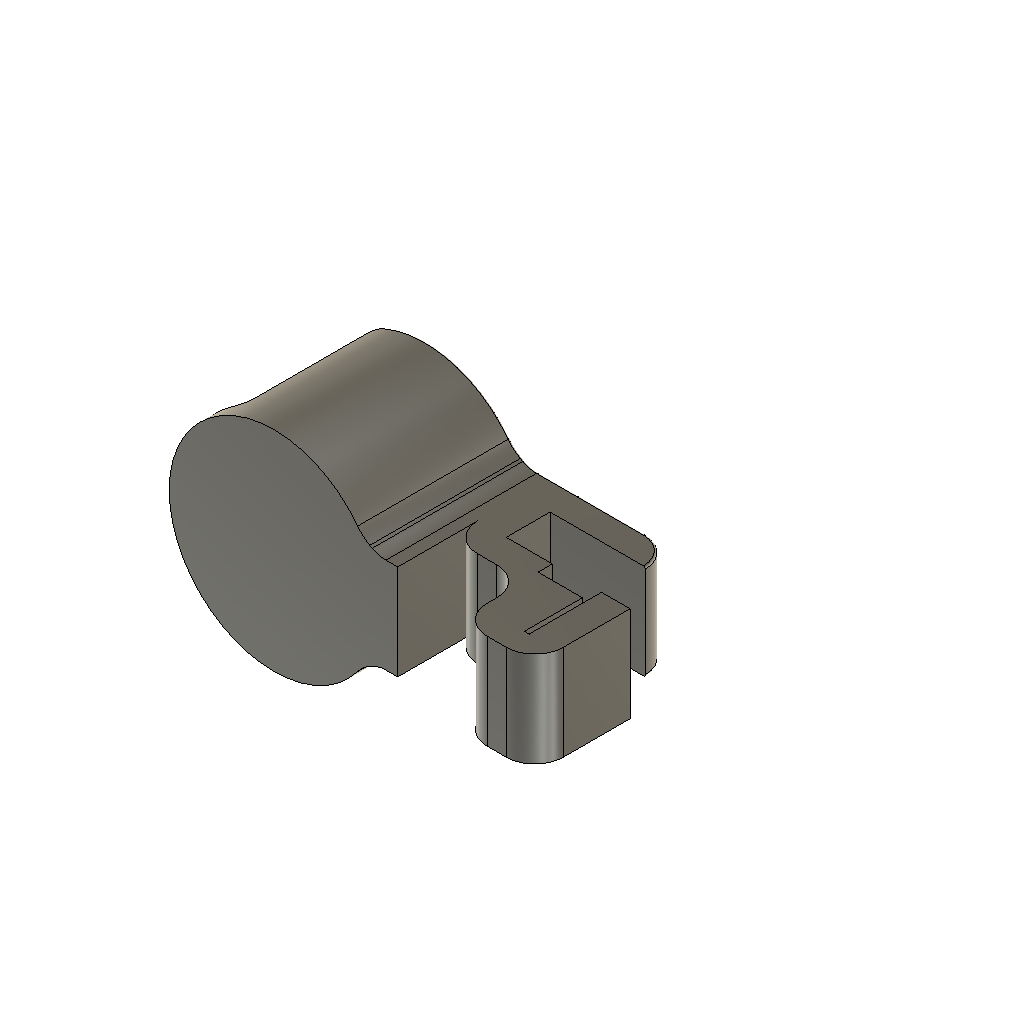
IkeaSkarstaTableGlassHolder (Autodesk Fusion 360 design; units mm, degrees)
part number: 2026-08-08-23-18-43-704
Autodesk Fusion 360 part; units mm, degrees
sketch "Sketch1" plane through (0, 0, 0) normal (0, 0, 1) x (1, 0, 0)
  line L0 (0, 0) -> (0, -38)
  line L1 (0, -38) -> (-2.5, -38)
  line L2 (-2.5, -38) -> (-2.5, -7.5)
  line L3 (-2.5, -7.5) -> (-25.8, -7.5)
  line L4 (-25.8, -7.5) -> (-25.8, 0)
  line L5 (-25.8, 0) -> (-50, 0)
  line L6 (-50, 0) -> (-50, 23)
  line L7 (-50, 23) -> (0, 23)
  line L8 (15, 0) -> (15, -38)
  line L9 (-50, 38) -> (-15, 38)
  line L10 (15, 0) -> (0, 0)
  arc A0 (0, 23) -> (-15, 38) centre (-15, 23) ccw
  line L11 (-64.9913, 38.0024) -> (-50, 38)
  line L12 (-64.9913, 38.0024) -> (-64.9976, 0.0024)
  line L13 (15, -38) -> (15, -35)
  line L14 (0, -50) -> (-10, -50)
  line L15 (-25, -35) -> (-25, -30)
  line L16 (-40, -15) -> (-49.9976, -15)
  arc A1 (-25, -30) -> (-40, -15) centre (-40, -30) ccw
  arc A2 (-64.9976, 0.0024) -> (-49.9976, -15) centre (-49.9976, 0) ccw
  arc A3 (-25, -35) -> (-10, -50) centre (-10, -35) ccw
  arc A4 (0, -50) -> (15, -35) centre (0, -35) ccw
  point P0 (-50, -80)
  dimension "d1" = 38
  dimension "d2" = 2.5
  dimension "d3" = 30.5
  dimension "d4" = 23.3
  dimension "d5" = 24.2
  dimension "d9" = 23
  dimension "d11" = 15
  dimension "d33" = 15
  dimension "d34" = 15
  dimension "d35" = 15
  dimension "d36" = 15
  constraint coincident L0.start L10.end
  constraint vertical L0
  constraint perpendicular L0 L1
  constraint perpendicular L1 L2
  constraint perpendicular L2 L3
  constraint perpendicular L3 L4
  constraint perpendicular L4 L5
  constraint perpendicular L5 L6
  constraint perpendicular L6 L7
  constraint perpendicular L0 L10
  constraint tangent L9 A0
  constraint coincident L7.end A0.start
  constraint perpendicular L11 L12
  constraint parallel L8 L13
  constraint perpendicular L13 L14
  constraint perpendicular L14 L15
  constraint parallel L14 L16
  constraint tangent L15 A1
  constraint tangent L16 A1
  constraint tangent L12 A2
  constraint tangent L16 A2
  constraint tangent L14 A3
  constraint tangent L15 A3
  constraint tangent L13 A4
  constraint tangent L14 A4
  measures "d1" distance of L0.start L0.end
  measures "d2" distance of L0.end L1.end
  measures "d3" distance of L1.end L2.end
  measures "d4" distance of L2.end L3.end
  measures "d5" distance of L4.end L5.end
  measures "d9" distance of L5.end L6.end
  measures "d11" radius of A0
  measures "d33" radius of A1
  measures "d34" radius of A2
  measures "d35" radius of A3
  measures "d36" radius of A4
extrude "Extrude5" add sketch "Sketch1" along normal blind 50
sketch "Sketch3" plane through (0.0062, 37.9918, 0) normal (0.000163, 1, 0) x (-1, 0.000163, 0)
  line L0 (50.0062, 0) -> (64.9976, 0)
  line L1 (64.9976, 0) -> (64.9976, 50)
  line L2 (64.9976, 50) -> (50.0062, 50)
  line L3 (50.0062, 50) -> (50.0062, 0)
  line L4 (64.9976, 50) -> (71.1728, 50)
  line L5 (71.1728, 0) -> (64.9976, 0)
  line L6 (64.9976, 0) -> (64.9976, 50)
  line L7 (157, 25) -> (-15, 25) construction
  line L8 (78.3553, 51.8314) -> (79.6476, 52.5363)
  line L9 (78.3553, -1.8314) -> (79.6476, -2.5363)
  arc A0 (71.1728, 50) -> (78.3553, 51.8314) centre (71.1728, 65) ccw
  arc A1 (78.3553, -1.8314) -> (71.1728, 0) centre (71.1728, -15) ccw
  arc A2 (86.052, -8.0692) -> (86.052, 58.0692) centre (130, 25) ccw
  circle A3 centre (130, 25) radius 52.5
  arc A4 (79.6476, 52.5363) -> (86.052, 58.0692) centre (70.0709, 70.0944) ccw
  arc A5 (86.052, -8.0692) -> (79.6476, -2.5363) centre (70.0709, -20.0944) ccw
  point P0 (74.9976, 50)
  point P1 (74.9976, 0)
  dimension "d39" = 50
  dimension "d40" = 10
  dimension "d41" = 110
  dimension "d42" = 15
  dimension "d43" = 15
  dimension "d44" = 105
  dimension "d45" = 20
  dimension "d46" = 20
  constraint horizontal L4
  constraint horizontal L5
  constraint vertical L6
  constraint coincident L1.end L2.start
  constraint perpendicular L3 L7
  constraint coincident A2.centre L7
  constraint coincident P0 L4
  constraint coincident P0 L8
  constraint tangent L4 A0
  constraint tangent L8 A0
  constraint coincident P1 L5
  constraint coincident P1 L9
  constraint tangent L5 A1
  constraint tangent L9 A1
  constraint concentric A2 A3
  constraint tangent L8 A4
  constraint tangent A2 A4
  constraint tangent L9 A5
  constraint tangent A2 A5
  measures "d39" distance of P0 P1
  measures "d40" distance of L1.end P0
  measures "d41" diameter of A2
  measures "d42" radius of A0
  measures "d43" radius of A1
  measures "d44" diameter of A3
  measures "d45" radius of A4
  measures "d46" radius of A5
extrude "Extrude6" add sketch "Sketch3" against normal blind 80 contours L1 L4 L5 L6 L8 L9 A0 A1 A2 A4 A5 | A3
extrude "Extrude7" cut sketch "Sketch3" against normal blind 75 contours A3
fillet "Fillet4" radius 5 1 edges at (-81.0589, -36.9949, 43.9848)
sketch "Sketch4" plane through (0.0062, 37.9918, 0) normal (0.000163, 1, 0) x (-1, 0.000163, 0)
  line L0 (50.0062, 50) -> (50.0062, 0)
  line L1 (130, 25) -> (179.4975, -24.4975)
  line L2 (179.4975, -24.4975) -> (190.1041, -13.8909)
  line L3 (190.1041, -13.8909) -> (140.6066, 35.6066)
  line L4 (140.6066, 35.6066) -> (130, 25)
  line L5 (168.8909, -35.1041) -> (119.3934, 14.3934)
  line L6 (119.3934, 14.3934) -> (130, 25)
  line L7 (179.4975, -24.4975) -> (168.8909, -35.1041)
  circle A0 centre (130, 25) radius 52.5
  line L8 (50.0062, 0) -> (71.1728, 0)
  arc A1 (78.3553, -1.8314) -> (71.1728, 0) centre (71.1728, -15) ccw
  line L9 (78.3553, -1.8314) -> (79.6476, -2.5363)
  arc A2 (86.052, -8.0692) -> (79.6476, -2.5363) centre (70.0709, -20.0944) ccw
  arc A3 (86.052, -8.0692) -> (86.052, 58.0692) centre (130, 25) ccw
  arc A4 (79.6476, 52.5363) -> (86.052, 58.0692) centre (70.0709, 70.0944) ccw
  line L10 (79.6476, 52.5363) -> (78.3553, 51.8314)
  arc A5 (71.1728, 50) -> (78.3553, 51.8314) centre (71.1728, 65) ccw
  line L11 (71.1728, 50) -> (50.0062, 50)
  line L12 (179.4975, 74.4975) -> (190.1041, 63.8909)
  line L13 (190.1041, 63.8909) -> (140.6066, 14.3934)
  line L14 (140.6066, 14.3934) -> (130, 25)
  line L15 (179.4975, 74.4975) -> (168.8909, 85.1041)
  line L16 (168.8909, 85.1041) -> (119.3934, 35.6066)
  line L17 (119.3934, 35.6066) -> (130, 25)
  dimension "d55" = 15
  dimension "d62" = 70
  dimension "d63" = 15
  constraint symmetric L4.end L1 L6.end
  constraint symmetric L2.start L1 L7.start
  constraint symmetric L2.end L1 L5.start
  constraint symmetric L3.end L1 L5.end
  constraint coincident L1.start L4.end
  measures "d55" distance of L1.start L3.end
  measures "d62" distance of L1.start L12.start
  measures "d63" distance of L1.start L13.end
extrude "Extrude9" cut sketch "Sketch4" against normal blind 70 contours L1 L5 A0 A3 | L1 L3 A0 A3
extrude "Extrude10" cut sketch "Sketch4" against normal blind 70 contours A0 A3 L13 L16
fillet "Fillet6" radius 5 8 edges at (-155.8947, -31.9827, 72.1027) (-155.8833, 38.0173, 72.1027) (-177.0965, 38.0207, 50.8895) (-177.0965, 38.0207, -0.8895) (-155.8833, 38.0173, -22.1027) (-155.8947, -31.9827, -22.1027) (-177.1079, -31.9793, -0.8895) (-177.1079, -31.9793, 50.8895)
fillet "BackPlaneFillet" radius 1 409 edges at (-77.4938, 38.0045, 25) (-153.5481, 36.6089, 71.9197) (-154.9685, 3.0171, 71.1822) (-156.3168, -30.5346, 70.4306) (-167.1283, -31.9809, 62.1231) (-175.4356, -30.5314, 51.3118) (-176.1817, 3.0206, 49.969) (-176.9137, 36.6127, 48.5541) (-182.4938, 38.0216, 25) (-176.9137, 36.6127, 1.4459) (-176.1817, 3.0206, 0.031) (-175.4356, -30.5314, -1.3118) (-167.1283, -31.9809, -12.1231) (-156.3168, -30.5346, -20.4306) (-154.9685, 3.0171, -21.1822) (-153.5481, 36.6089, -21.9197) (-116.054, 38.0108, 78.2042) (-83.1396, 38.0054, 54.9601) (-78.9953, 38.0047, 52.1839) (-74.8728, 38.0041, 50.4651) (-60.5833, 38.0017, 50) (-32.5, 38, 50) (-4.3934, 33.6066, 50) (-155.4111, 36.6038, 73.7747) (-156.8095, 3.0174, 73.0232) (-158.142, -30.5328, 72.2579) (-168.8961, -31.9806, 63.8909) (-177.263, -30.5296, 53.1369) (-178.0227, 3.0209, 51.81) (-178.7688, 36.6076, 50.417) (-184.9938, 38.022, 25) (-178.7686, 36.6073, -0.4174) (-178.0227, 3.0209, -1.81) (-177.263, -30.5296, -3.1369) (-168.8961, -31.9806, -13.8909) (-158.142, -30.5328, -22.2579) (-156.8095, 3.0174, -23.0232) (-155.4111, 36.6038, -23.7747) (-116.054, 38.0108, -28.2042) (-83.1396, 38.0054, -4.9601) (-78.9953, 38.0047, -2.1839) (-74.8728, 38.0041, -0.4651) (-60.5833, 38.0017, 0) (-32.5, 38, 0) (-4.3934, 33.6066, 0) (-83.1396, 38.0054, 54.9601) (-116.054, 38.0108, 78.2042) (-155.4111, 36.6038, 73.7747) (-156.8095, 3.0174, 73.0232) (-158.142, -30.5328, 72.2579) (-168.8961, -31.9806, 63.8909) (-177.263, -30.5296, 53.1369) (-178.0227, 3.0209, 51.81) (-178.7688, 36.6076, 50.417) (-184.9938, 38.022, 25) (-178.7686, 36.6073, -0.4174) (-178.0227, 3.0209, -1.81) (-177.263, -30.5296, -3.1369) (-168.8961, -31.9806, -13.8909) (-158.142, -30.5328, -22.2579) (-156.8095, 3.0174, -23.0232) (-155.4111, 36.6038, -23.7747) (-116.054, 38.0108, -28.2042) (-83.1396, 38.0054, -4.9601) (-78.9953, 38.0047, -2.1839) (-74.8728, 38.0041, -0.4651) (-60.5833, 38.0017, 0) (-32.5, 38, 0) (-4.3934, 33.6066, 0) (-78.9953, 38.0047, 52.1839) (-74.8728, 38.0041, 50.4651) (-60.5833, 38.0017, 50) (-32.5, 38, 50) (-4.3934, 33.6066, 50) (-78.9953, 38.0047, 52.1839) (-83.1396, 38.0054, 54.9601) (-116.054, 38.0108, 78.2042) (-155.4111, 36.6038, 73.7747) (-156.8095, 3.0174, 73.0232) (-158.142, -30.5328, 72.2579) (-168.8961, -31.9806, 63.8909) (-177.263, -30.5296, 53.1369) (-178.0227, 3.0209, 51.81) (-178.7688, 36.6076, 50.417) (-184.9938, 38.022, 25) (-178.7686, 36.6073, -0.4174) (-178.0227, 3.0209, -1.81) (-177.263, -30.5296, -3.1369) (-168.8961, -31.9806, -13.8909) (-158.142, -30.5328, -22.2579) (-156.8095, 3.0174, -23.0232) (-155.4111, 36.6038, -23.7747) (-116.054, 38.0108, -28.2042) (-83.1396, 38.0054, -4.9601) (-78.9953, 38.0047, -2.1839) (-74.8728, 38.0041, -0.4651) (-60.5833, 38.0017, 0) (-32.5, 38, 0) (-4.3934, 33.6066, 0) (-74.8728, 38.0041, 50.4651) (-60.5833, 38.0017, 50) (-32.5, 38, 50) (-4.3934, 33.6066, 50) (-74.8728, 38.0041, 50.4651) (-78.9953, 38.0047, 52.1839) (-83.1396, 38.0054, 54.9601) (-116.054, 38.0108, 78.2042) (-155.4111, 36.6038, 73.7747) (-156.8095, 3.0174, 73.0232) (-158.142, -30.5328, 72.2579) (-168.8961, -31.9806, 63.8909) (-177.263, -30.5296, 53.1369) (-178.0227, 3.0209, 51.81) (-178.7688, 36.6076, 50.417) (-184.9938, 38.022, 25) (-178.7686, 36.6073, -0.4174) (-178.0227, 3.0209, -1.81) (-177.263, -30.5296, -3.1369) (-168.8961, -31.9806, -13.8909) (-158.142, -30.5328, -22.2579) (-156.8095, 3.0174, -23.0232) (-155.4111, 36.6038, -23.7747) (-116.054, 38.0108, -28.2042) (-83.1396, 38.0054, -4.9601) (-78.9953, 38.0047, -2.1839) (-74.8728, 38.0041, -0.4651) (-60.5833, 38.0017, 0) (-32.5, 38, 0) (-4.3934, 33.6066, 0) (-60.5833, 38.0017, 50) (-32.5, 38, 50) (-4.3934, 33.6066, 50) (-60.5833, 38.0017, 50) (-74.8728, 38.0041, 50.4651) (-78.9953, 38.0047, 52.1839) (-83.1396, 38.0054, 54.9601) (-116.054, 38.0108, 78.2042) (-155.4111, 36.6038, 73.7747) (-156.8095, 3.0174, 73.0232) (-158.142, -30.5328, 72.2579) (-168.8961, -31.9806, 63.8909) (-177.263, -30.5296, 53.1369) (-178.0227, 3.0209, 51.81) (-178.7688, 36.6076, 50.417) (-184.9938, 38.022, 25) (-178.7686, 36.6073, -0.4174) (-178.0227, 3.0209, -1.81) (-177.263, -30.5296, -3.1369) (-168.8961, -31.9806, -13.8909) (-158.142, -30.5328, -22.2579) (-156.8095, 3.0174, -23.0232) (-155.4111, 36.6038, -23.7747) (-116.054, 38.0108, -28.2042) (-83.1396, 38.0054, -4.9601) (-78.9953, 38.0047, -2.1839) (-74.8728, 38.0041, -0.4651) (-60.5833, 38.0017, 0) (-32.5, 38, 0) (-4.3934, 33.6066, 0) (-32.5, 38, 50) (-4.3934, 33.6066, 50) (-60.5833, 38.0017, 0) (-32.5, 38, 0) (-4.3934, 33.6066, 0) (-74.8728, 38.0041, -0.4651) (-78.9953, 38.0047, -2.1839) (-83.1396, 38.0054, -4.9601) (-116.054, 38.0108, -28.2042) (-155.4111, 36.6038, -23.7747) (-156.8095, 3.0174, -23.0232) (-158.142, -30.5328, -22.2579) (-168.8961, -31.9806, -13.8909) (-177.263, -30.5296, -3.1369) (-178.0227, 3.0209, -1.81) (-178.7686, 36.6073, -0.4174) (-184.9938, 38.022, 25) (-178.7688, 36.6076, 50.417) (-178.0227, 3.0209, 51.81) (-177.263, -30.5296, 53.1369) (-168.8961, -31.9806, 63.8909) (-158.142, -30.5328, 72.2579) (-156.8095, 3.0174, 73.0232) (-155.4111, 36.6038, 73.7747) (-116.054, 38.0108, 78.2042) (-83.1396, 38.0054, 54.9601) (-78.9953, 38.0047, 52.1839) (-74.8728, 38.0041, 50.4651) (-60.5833, 38.0017, 50) (-32.5, 38, 50) (-4.3934, 33.6066, 50) (-74.8728, 38.0041, -0.4651) (-60.5833, 38.0017, 0) (-32.5, 38, 0) (-4.3934, 33.6066, 0) (-78.9953, 38.0047, -2.1839) (-83.1396, 38.0054, -4.9601) (-116.054, 38.0108, -28.2042) (-155.4111, 36.6038, -23.7747) (-156.8095, 3.0174, -23.0232) (-158.142, -30.5328, -22.2579) (-168.8961, -31.9806, -13.8909) (-177.263, -30.5296, -3.1369) (-178.0227, 3.0209, -1.81) (-178.7686, 36.6073, -0.4174) (-184.9938, 38.022, 25) (-178.7688, 36.6076, 50.417) (-178.0227, 3.0209, 51.81) (-177.263, -30.5296, 53.1369) (-168.8961, -31.9806, 63.8909) (-158.142, -30.5328, 72.2579) (-156.8095, 3.0174, 73.0232) (-155.4111, 36.6038, 73.7747) (-116.054, 38.0108, 78.2042) (-83.1396, 38.0054, 54.9601) (-78.9953, 38.0047, 52.1839) (-74.8728, 38.0041, 50.4651) (-60.5833, 38.0017, 50) (-32.5, 38, 50) (-4.3934, 33.6066, 50) (-78.9953, 38.0047, -2.1839) (-83.1396, 38.0054, -4.9601) (-116.054, 38.0108, -28.2042) (-155.4111, 36.6038, -23.7747) (-156.8095, 3.0174, -23.0232) (-158.142, -30.5328, -22.2579) (-168.8961, -31.9806, -13.8909) (-177.263, -30.5296, -3.1369) (-178.0227, 3.0209, -1.81) (-178.7686, 36.6073, -0.4174) (-184.9938, 38.022, 25) (-178.7688, 36.6076, 50.417) (-178.0227, 3.0209, 51.81) (-177.263, -30.5296, 53.1369) (-168.8961, -31.9806, 63.8909) (-158.142, -30.5328, 72.2579) (-156.8095, 3.0174, 73.0232) (-155.4111, 36.6038, 73.7747) (-116.054, 38.0108, 78.2042) (-83.1396, 38.0054, 54.9601) (-78.9953, 38.0047, 52.1839) (-74.8728, 38.0041, 50.4651) (-60.5833, 38.0017, 50) (-32.5, 38, 50) (-4.3934, 33.6066, 50) (-74.8728, 38.0041, -0.4651) (-60.5833, 38.0017, 0) (-32.5, 38, 0) (-4.3934, 33.6066, 0) (-83.1396, 38.0054, -4.9601) (-78.9953, 38.0047, -2.1839) (-74.8728, 38.0041, -0.4651) (-60.5833, 38.0017, 0) (-32.5, 38, 0) (-4.3934, 33.6066, 0) (-116.054, 38.0108, -28.2042) (-155.4111, 36.6038, -23.7747) (-156.8095, 3.0174, -23.0232) (-158.142, -30.5328, -22.2579) (-168.8961, -31.9806, -13.8909) (-177.263, -30.5296, -3.1369) (-178.0227, 3.0209, -1.81) (-178.7686, 36.6073, -0.4174) (-184.9938, 38.022, 25) (-178.7688, 36.6076, 50.417) (-178.0227, 3.0209, 51.81) (-177.263, -30.5296, 53.1369) (-168.8961, -31.9806, 63.8909) (-158.142, -30.5328, 72.2579) (-156.8095, 3.0174, 73.0232) (-155.4111, 36.6038, 73.7747) (-116.054, 38.0108, 78.2042) (-83.1396, 38.0054, 54.9601) (-78.9953, 38.0047, 52.1839) (-74.8728, 38.0041, 50.4651) (-60.5833, 38.0017, 50) (-32.5, 38, 50) (-4.3934, 33.6066, 50) (-116.054, 38.0108, -28.2042) (-155.4111, 36.6038, -23.7747) (-156.8095, 3.0174, -23.0232) (-158.142, -30.5328, -22.2579) (-168.8961, -31.9806, -13.8909) (-177.263, -30.5296, -3.1369) (-178.0227, 3.0209, -1.81) (-178.7686, 36.6073, -0.4174) (-184.9938, 38.022, 25) (-178.7688, 36.6076, 50.417) (-178.0227, 3.0209, 51.81) (-177.263, -30.5296, 53.1369) (-168.8961, -31.9806, 63.8909) (-158.142, -30.5328, 72.2579) (-156.8095, 3.0174, 73.0232) (-155.4111, 36.6038, 73.7747) (-116.054, 38.0108, 78.2042) (-83.1396, 38.0054, 54.9601) (-78.9953, 38.0047, 52.1839) (-74.8728, 38.0041, 50.4651) (-60.5833, 38.0017, 50) (-32.5, 38, 50) (-4.3934, 33.6066, 50) (-83.1396, 38.0054, -4.9601) (-78.9953, 38.0047, -2.1839) (-74.8728, 38.0041, -0.4651) (-60.5833, 38.0017, 0) (-32.5, 38, 0) (-4.3934, 33.6066, 0) (-184.9938, 38.022, 25) (-178.7688, 36.6076, 50.417) (-178.0227, 3.0209, 51.81) (-177.263, -30.5296, 53.1369) (-168.8961, -31.9806, 63.8909) (-158.142, -30.5328, 72.2579) (-156.8095, 3.0174, 73.0232) (-155.4111, 36.6038, 73.7747) (-116.054, 38.0108, 78.2042) (-83.1396, 38.0054, 54.9601) (-78.9953, 38.0047, 52.1839) (-74.8728, 38.0041, 50.4651) (-60.5833, 38.0017, 50) (-32.5, 38, 50) (-4.3934, 33.6066, 50) (-178.7686, 36.6073, -0.4174) (-178.0227, 3.0209, -1.81) (-177.263, -30.5296, -3.1369) (-168.8961, -31.9806, -13.8909) (-158.142, -30.5328, -22.2579) (-156.8095, 3.0174, -23.0232) (-155.4111, 36.6038, -23.7747) (-116.054, 38.0108, -28.2042) (-83.1396, 38.0054, -4.9601) (-78.9953, 38.0047, -2.1839) (-74.8728, 38.0041, -0.4651) (-60.5833, 38.0017, 0) (-32.5, 38, 0) (-4.3934, 33.6066, 0) (-182.4938, 38.0216, 25) (-176.9137, 36.6127, 1.4459) (-176.1817, 3.0206, 0.031) (-175.4356, -30.5314, -1.3118) (-167.1283, -31.9809, -12.1231) (-156.3168, -30.5346, -20.4306) (-154.9685, 3.0171, -21.1822) (-153.5481, 36.6089, -21.9197) (-77.4938, 38.0045, 25) (-153.5481, 36.6089, 71.9197) (-154.9685, 3.0171, 71.1822) (-156.3168, -30.5346, 70.4306) (-167.1283, -31.9809, 62.1231) (-175.4356, -30.5314, 51.3118) (-176.1817, 3.0206, 49.969) (-176.9137, 36.6127, 48.5541) (-32.5, 38, 0) (-4.3934, 33.6066, 0) (-60.5833, 38.0017, 0) (-74.8728, 38.0041, -0.4651) (-78.9953, 38.0047, -2.1839) (-83.1396, 38.0054, -4.9601) (-116.054, 38.0108, -28.2042) (-155.4111, 36.6038, -23.7747) (-156.8095, 3.0174, -23.0232) (-158.142, -30.5328, -22.2579) (-168.8961, -31.9806, -13.8909) (-177.263, -30.5296, -3.1369) (-178.0227, 3.0209, -1.81) (-178.7686, 36.6073, -0.4174) (-184.9938, 38.022, 25) (-178.7688, 36.6076, 50.417) (-178.0227, 3.0209, 51.81) (-177.263, -30.5296, 53.1369) (-168.8961, -31.9806, 63.8909) (-158.142, -30.5328, 72.2579) (-156.8095, 3.0174, 73.0232) (-155.4111, 36.6038, 73.7747) (-116.054, 38.0108, 78.2042) (-83.1396, 38.0054, 54.9601) (-78.9953, 38.0047, 52.1839) (-74.8728, 38.0041, 50.4651) (-60.5833, 38.0017, 50) (-32.5, 38, 50) (-4.3934, 33.6066, 50) (-32.5, 38, 50) (-60.5833, 38.0017, 50) (-74.8728, 38.0041, 50.4651) (-78.9953, 38.0047, 52.1839) (-83.1396, 38.0054, 54.9601) (-116.054, 38.0108, 78.2042) (-155.4111, 36.6038, 73.7747) (-156.8095, 3.0174, 73.0232) (-158.142, -30.5328, 72.2579) (-168.8961, -31.9806, 63.8909) (-177.263, -30.5296, 53.1369) (-178.0227, 3.0209, 51.81) (-178.7688, 36.6076, 50.417) (-184.9938, 38.022, 25) (-178.7686, 36.6073, -0.4174) (-178.0227, 3.0209, -1.81) (-177.263, -30.5296, -3.1369) (-168.8961, -31.9806, -13.8909) (-158.142, -30.5328, -22.2579) (-156.8095, 3.0174, -23.0232) (-155.4111, 36.6038, -23.7747) (-116.054, 38.0108, -28.2042) (-83.1396, 38.0054, -4.9601) (-78.9953, 38.0047, -2.1839) (-74.8728, 38.0041, -0.4651) (-60.5833, 38.0017, 0) (-32.5, 38, 0) (-4.3934, 33.6066, 0) (-4.3934, 33.6066, 50)
equation "d3 = 33 mm - 2.5 mm"
equation "d5 = 47.2 mm - 23 mm"
